TempControl (Autodesk Fusion 360 design; units mm, degrees)
part number: 2026-04-30-21-48-59-298
Autodesk Fusion 360 part; units mm, degrees
sketch "Sketch1" plane through (0, 0, 0) normal (0, 0, 1) x (1, 0, 0)
  line L0 (-28.75, 12.8) -> (28.75, 12.8)
  line L1 (28.75, 12.8) -> (28.75, -12.8)
  line L2 (28.75, -12.8) -> (-28.75, -12.8)
  line L3 (-28.75, -12.8) -> (-28.75, 12.8)
  line L4 (0, 1.75) -> (0, 22.5)
  line L5 (1.75, 0) -> (22.5, 0)
  dimension "d1" = 57.5
  dimension "d2" = 25.6
  constraint horizontal L0
  constraint vertical L1
  constraint horizontal L2
  constraint vertical L3
  constraint symmetric L1 L3 L4
  constraint symmetric L0 L2 L5
  measures "d1" distance of L0.start L0.end
  measures "d2" distance of L0.end L1.end
extrude "Extrude1" add sketch "Sketch1" along normal blind 15
sketch "Sketch2" plane through (0, 0, 15) normal (0, 0, 1) x (-1, 0, 0)
  line L0 (28.75, 12.8) -> (-28.75, 12.8)
  line L1 (-28.75, 12.8) -> (-28.75, -12.8)
  line L2 (-28.75, -12.8) -> (28.75, -12.8)
  line L3 (28.75, -12.8) -> (28.75, 12.8)
  line L4 (29.95, -14.25) -> (-29.95, -14.25)
  line L5 (-29.95, -14.25) -> (-29.95, 14.25)
  line L6 (-29.95, 14.25) -> (29.95, 14.25)
  line L7 (29.95, 14.25) -> (29.95, -14.25)
  line L8 (-1.75, 0) -> (-22.5, 0)
  line L9 (0, -1.75) -> (0, -22.5)
  dimension "d5" = 59.9
  dimension "d6" = 28.5
  constraint horizontal L4
  constraint vertical L5
  constraint horizontal L6
  constraint vertical L7
  constraint symmetric L4 L6 L8
  constraint symmetric L5 L7 L9
  measures "d5" distance of L4.start L4.end
  measures "d6" distance of L4.end L5.end
extrude "Extrude2" add sketch "Sketch2" along normal blind 2.5 contours L0 L1 L2 L3 | L4 L5 L6 L7
